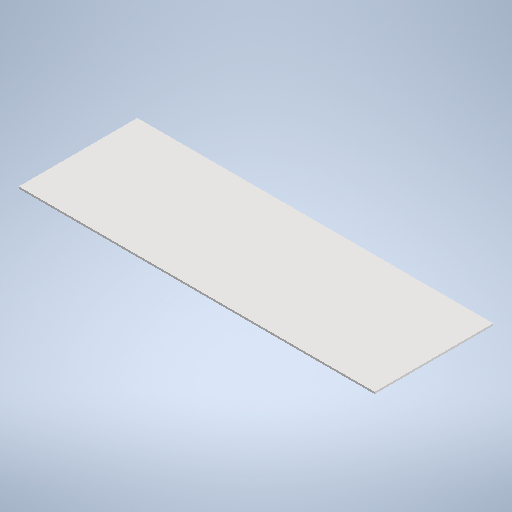
# Autodesk Inventor part: RDS-3003 Deck 750x250
Saved by Autodesk Inventor 2026 (Build 300175000, 175)
## iProperties
Created: 2026-10-28
Part Number: RDS-3003 Deck 750x250
Material: Типовые
Document SubType Name: Modeling
Designer: user
Density: 1 g/cm^3
Appearance: По умолчанию
Author: user
Autodesk Inventor part; units mm, degrees
ref_plane "YZ Plane" through (0, 0, 0) normal (1, 0, 0) x (0, 1, 0)
ref_plane "XZ Plane" through (0, 0, 0) normal (0, 1, 0) x (-1, 0, 0)
ref_plane "XY Plane" through (0, 0, 0) normal (0, 0, 1) x (1, 0, 0)
sketch "Эскиз1" plane through (0, 0, 0) normal (0, 1, 0) x (-1, 0, 0)
  line L0 (375, 125) -> (-375, 125)
  line L1 (-375, 125) -> (-375, -125)
  line L2 (-375, -125) -> (375, -125)
  line L3 (375, -125) -> (375, 125)
  line L4 (375, 125) -> (-375, -125) construction
  line L5 (-375, 125) -> (375, -125) construction
  point P0 (0, 0)
  dimension "d0" = 750
  dimension "d1" = 250
  constraints: 12 end point, 2 midpoint, 2 parallel, 1 horizontal, 1 perpendicular
  measures "d0" distance of L2.end L1.end
  measures "d1" distance of L1.end L0.end
extrude "Выдавливание1" add sketch "Эскиз1" along normal blind 4
